Autodesk Fusion 360 part; units mm, degrees
(part 2 of 2)
equation "cable_clip_open_k = 0.75" comment "Snap opening = open_k x cable diameter (as XIAO open_k)"
equation "cable_clip_stem = 5 mm" comment "Stem width (as XIAO post_w)"
equation "cable_clip_emb = 0.6 mm" comment "Ring sunk into the post wall (as XIAO clip2_emb)"
equation "cable_clip_y = 9 mm" comment "Clip offset on the -X face from the post centre, clear of the rib and the window"
equation "foot_clearance = 0.25 mm" comment "Gridfinity foot = measured socket offset inwards by this, every face (standard bin 0.25)"
equation "foot_clearance_c025 = 0.25 mm" comment "Foot test piece clearance per side"
equation "foot_clearance_c035 = 0.35 mm" comment "Foot test piece clearance per side"
equation "leg_rib_pad_margin = 0 mm" comment "Leg pad reaches the rib tips (gusset_length) on the -X/-Y sides plus this"
equation "gf_fit_adjust = 0 mm" comment "Extra inward offset of the standard Gridfinity foot per side (0 = standard)"
equation "cal_height = 21 mm" comment "Calibration bin height from the foot bottom, 3 Gridfinity units"
equation "cal_floor = 7 mm" comment "Floor top above the foot bottom (BASE_HEIGHT of the generator)"
equation "cal_pocket = 37 mm" comment "Inner pocket for the 4-corner suction cup method (cup ~22 mm effective -> ~15 mm travel)"
equation "cal_pocket_r = 0.5 mm" comment "Inner pocket corner radius"
equation "cal_cross_w = 1 mm" comment "Centre cross line width"
equation "cal_cross_depth = 0.6 mm" comment "Centre cross depth (3 layers at 0.2)"
equation "cal_cross_len = 35 mm" comment "Centre cross line length"
named bodies: "webcam_post_lower", "webcam_post_upper", "clip_lower_leg_48.5x42.04x10.88", "camera_head_lens", "webcam_post_leg"
